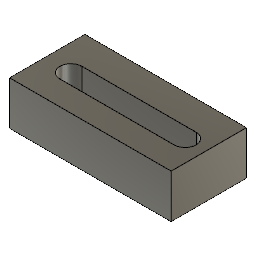
Vis v1 (Autodesk Fusion 360 design; units mm, degrees)
Autodesk Fusion 360 part; units mm, degrees
sketch "Sketch1" plane through (0, 0, 0) normal (0, 0, 1) x (1, 0, 0)
  line L0 (0, 0) -> (18.4149, 0)
  line L1 (18.4149, 0) -> (18.4149, 8.5839)
  line L2 (18.4149, 8.5839) -> (0, 8.5839)
  line L3 (0, 8.5839) -> (0, 0)
  constraint horizontal L0
  constraint vertical L1
  constraint horizontal L2
  constraint vertical L3
  constraint coincident L0.start L3.end
extrude "Extrude1" add sketch "Sketch1" along normal blind 5
sketch "Sketch2" plane through (0, 0, 5) normal (0, 0, 1) x (-1, 0, 0)
  line L0 (0, -8.5839) -> (0, 0)
  line L1 (0, 0) -> (-18.4149, 0)
  line L2 (-18.4149, 0) -> (-18.4149, -8.5839)
  line L3 (-18.4149, -8.5839) -> (0, -8.5839)
  circle A0 centre (-3, -4) radius 1.2501
  circle A1 centre (-16, -4) radius 1.25
  line L4 (-3.0104, -5.25) -> (-16.0446, -5.25)
  line L5 (-16.0446, -5.25) -> (-16.0446, -2.7508)
  line L6 (-16.0446, -2.7508) -> (-3.0104, -2.7508)
  line L7 (-3.0104, -2.7508) -> (-3.0104, -5.25)
  dimension "d3" = 2.5
  constraint horizontal L4
  constraint vertical L5
  constraint horizontal L6
  constraint vertical L7
  constraint coincident A1 L5.end
  constraint coincident A0 L4.start
  measures "d3" diameter of A1
extrude "Extrude2" cut sketch "Sketch2" against normal blind 5 contours A0 L6 L7 | A0 A1 L4 L6 | A0 L6 L7 | A1 L4 L5 | A1 L5 L6 | A1 L5
